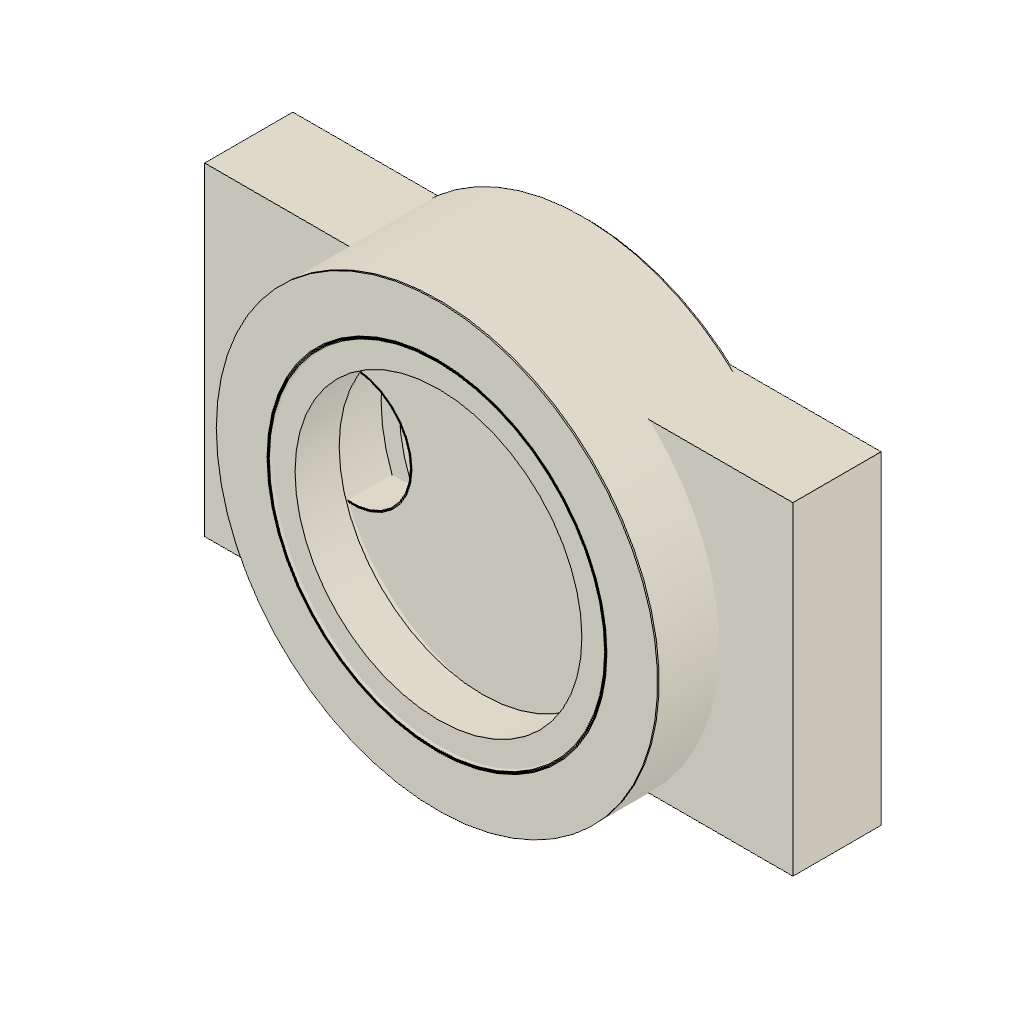
14-bearing-and-fastener-fit-trials (Autodesk Fusion 360 design; units mm, degrees)
part number: 2026-11-02-20-20-23-688
part number: 2026-11-02-20-20-23-889
part number: 2026-11-02-20-20-23-959
part number: 2026-11-02-20-20-24-041
part number: 2026-11-02-20-20-24-142
part number: 2026-11-02-20-20-24-261
part number: 2026-11-02-20-20-24-400
part number: 2026-11-02-20-20-24-565
part number: 2026-11-02-20-20-24-753
part number: 2026-11-02-20-20-24-962
part number: 2026-11-02-20-20-25-426
part number: 2026-11-02-20-20-25-979
Autodesk Fusion 360 part; units mm, degrees
ref_plane "WorkPlane1" through (0, 0, 0) normal (0, 0, 1) x (1, 0, 0)
ref_plane "WorkPlane1" through (0, 0, 0) normal (0, 0, 1) x (1, 0, 0) in component "Seat 22.0 mouth down"
sketch "Coupon Blank sketch" plane through (0, 0, 0) normal (0, 0, 1) x (1, 0, 0) in component "Seat 22.0 mouth down"
  circle A0 centre (0, 0) radius 15
  dimension "d10" = 30
  measures "d10" diameter of A0
extrude "Coupon Blank" add sketch "Coupon Blank sketch" along normal blind 10.1 makes body 1 in component "Seat 22.0 mouth down"
ref_plane "WorkPlane2" through (0, 0, 0) normal (0, 0, 1) x (1, 0, 0) in component "Seat 22.0 mouth down"
sketch "Seal Relief sketch" plane through (0, 0, 0) normal (0, 0, 1) x (1, 0, 0) in component "Seat 22.0 mouth down"
  circle A0 centre (0, 0) radius 9.75
  dimension "d15" = 19.5
  measures "d15" diameter of A0
extrude "Seal Relief" cut sketch "Seal Relief sketch" along normal blind 10.1 bodies 1 in component "Seat 22.0 mouth down"
ref_plane "WorkPlane3" through (0, 0, 0) normal (0, 0, 1) x (1, 0, 0) in component "Seat 22.0 mouth down"
sketch "Seat 22.0 sketch" plane through (0, 0, 0) normal (0, 0, 1) x (1, 0, 0) in component "Seat 22.0 mouth down"
  circle A0 centre (0, 0) radius 11
  dimension "d20" = 22
  measures "d20" diameter of A0
extrude "Seat 22.0" cut sketch "Seat 22.0 sketch" along normal blind 7.1 bodies 1 in component "Seat 22.0 mouth down"
chamfer "Pocket Entry" distance 0.4 angle 45 1 edges at (-10.2556, -3.9778, 0) tangent chain off on bodies 1 in component "Seat 22.0 mouth down"
chamfer "Outer Bed Relief" distance 0.3 angle 45 1 edges at (-13.9849, -5.4242, 0) tangent chain off on bodies 1 in component "Seat 22.0 mouth down"
ref_plane "WorkPlane1" through (0, 0, 0) normal (0, 0, 1) x (1, 0, 0) in component "Seat 22.1 mouth down"
sketch "Coupon Blank sketch (2)" plane through (0, 0, 0) normal (0, 0, 1) x (1, 0, 0) in component "Seat 22.1 mouth down"
  circle A0 centre (0, 0) radius 15
  dimension "d27" = 30
  measures "d27" diameter of A0
extrude "Coupon Blank'" add sketch "Coupon Blank sketch (2)" along normal blind 10.1 separate body makes body 2 in component "Seat 22.1 mouth down"
ref_plane "WorkPlane2" through (0, 0, 0) normal (0, 0, 1) x (1, 0, 0) in component "Seat 22.1 mouth down"
sketch "Seal Relief sketch (2)" plane through (0, 0, 0) normal (0, 0, 1) x (1, 0, 0) in component "Seat 22.1 mouth down"
  circle A0 centre (0, 0) radius 9.75
  dimension "d32" = 19.5
  measures "d32" diameter of A0
extrude "Seal Relief'" cut sketch "Seal Relief sketch (2)" along normal blind 10.1 bodies 2 in component "Seat 22.1 mouth down"
ref_plane "WorkPlane3" through (0, 0, 0) normal (0, 0, 1) x (1, 0, 0) in component "Seat 22.1 mouth down"
sketch "Seat 22.1 sketch" plane through (0, 0, 0) normal (0, 0, 1) x (1, 0, 0) in component "Seat 22.1 mouth down"
  circle A0 centre (0, 0) radius 11.05
  dimension "d37" = 22.1
  measures "d37" diameter of A0
extrude "Seat 22.1" cut sketch "Seat 22.1 sketch" along normal blind 7.1 bodies 2 in component "Seat 22.1 mouth down"
chamfer "Pocket Entry'" distance 0.4 angle 45 1 edges at (-10.3022, -3.9959, 0) tangent chain off on bodies 2 in component "Seat 22.1 mouth down"
chamfer "Outer Bed Relief'" distance 0.3 angle 45 1 edges at (-13.9849, -5.4242, 0) tangent chain off on bodies 2 in component "Seat 22.1 mouth down"
ref_plane "WorkPlane1" through (0, 0, 0) normal (0, 0, 1) x (1, 0, 0) in component "Seat 22.2 mouth down"
sketch "Coupon Blank sketch (3)" plane through (0, 0, 0) normal (0, 0, 1) x (1, 0, 0) in component "Seat 22.2 mouth down"
  circle A0 centre (0, 0) radius 15
  dimension "d44" = 30
  measures "d44" diameter of A0
extrude "Coupon Blank''" add sketch "Coupon Blank sketch (3)" along normal blind 10.1 separate body makes body 3 in component "Seat 22.2 mouth down"
ref_plane "WorkPlane2" through (0, 0, 0) normal (0, 0, 1) x (1, 0, 0) in component "Seat 22.2 mouth down"
sketch "Seal Relief sketch (3)" plane through (0, 0, 0) normal (0, 0, 1) x (1, 0, 0) in component "Seat 22.2 mouth down"
  circle A0 centre (0, 0) radius 9.75
  dimension "d49" = 19.5
  measures "d49" diameter of A0
extrude "Seal Relief''" cut sketch "Seal Relief sketch (3)" along normal blind 10.1 bodies 3 in component "Seat 22.2 mouth down"
ref_plane "WorkPlane3" through (0, 0, 0) normal (0, 0, 1) x (1, 0, 0) in component "Seat 22.2 mouth down"
sketch "Seat 22.2 sketch" plane through (0, 0, 0) normal (0, 0, 1) x (1, 0, 0) in component "Seat 22.2 mouth down"
  circle A0 centre (0, 0) radius 11.1
  dimension "d54" = 22.2
  measures "d54" diameter of A0
extrude "Seat 22.2" cut sketch "Seat 22.2 sketch" along normal blind 7.1 bodies 3 in component "Seat 22.2 mouth down"
chamfer "Pocket Entry''" distance 0.4 angle 45 1 edges at (-10.3488, -4.0139, 0) tangent chain off on bodies 3 in component "Seat 22.2 mouth down"
chamfer "Outer Bed Relief''" distance 0.3 angle 45 1 edges at (-13.9849, -5.4242, 0) tangent chain off on bodies 3 in component "Seat 22.2 mouth down"
ref_plane "WorkPlane1" through (0, 0, 0) normal (0, 0, 1) x (1, 0, 0) in component "Seat 22.3 mouth down"
sketch "Coupon Blank sketch (4)" plane through (0, 0, 0) normal (0, 0, 1) x (1, 0, 0) in component "Seat 22.3 mouth down"
  circle A0 centre (0, 0) radius 15
  dimension "d61" = 30
  measures "d61" diameter of A0
extrude "Coupon Blank'''" add sketch "Coupon Blank sketch (4)" along normal blind 10.1 separate body makes body 4 in component "Seat 22.3 mouth down"
ref_plane "WorkPlane2" through (0, 0, 0) normal (0, 0, 1) x (1, 0, 0) in component "Seat 22.3 mouth down"
sketch "Seal Relief sketch (4)" plane through (0, 0, 0) normal (0, 0, 1) x (1, 0, 0) in component "Seat 22.3 mouth down"
  circle A0 centre (0, 0) radius 9.75
  dimension "d66" = 19.5
  measures "d66" diameter of A0
extrude "Seal Relief'''" cut sketch "Seal Relief sketch (4)" along normal blind 10.1 bodies 4 in component "Seat 22.3 mouth down"
ref_plane "WorkPlane3" through (0, 0, 0) normal (0, 0, 1) x (1, 0, 0) in component "Seat 22.3 mouth down"
sketch "Seat 22.3 sketch" plane through (0, 0, 0) normal (0, 0, 1) x (1, 0, 0) in component "Seat 22.3 mouth down"
  circle A0 centre (0, 0) radius 11.15
  dimension "d71" = 22.3
  measures "d71" diameter of A0
extrude "Seat 22.3" cut sketch "Seat 22.3 sketch" along normal blind 7.1 bodies 4 in component "Seat 22.3 mouth down"
chamfer "Pocket Entry'''" distance 0.4 angle 45 1 edges at (-10.3954, -4.032, 0) tangent chain off on bodies 4 in component "Seat 22.3 mouth down"
chamfer "Outer Bed Relief'''" distance 0.3 angle 45 1 edges at (-13.9849, -5.4242, 0) tangent chain off on bodies 4 in component "Seat 22.3 mouth down"
ref_plane "WorkPlane1" through (0, 0, 0) normal (0, 0, 1) x (1, 0, 0) in component "Seat 22.0 mouth up"
sketch "Coupon Blank sketch (5)" plane through (0, 0, 0) normal (0, 0, 1) x (1, 0, 0) in component "Seat 22.0 mouth up"
  circle A0 centre (0, 0) radius 15
  dimension "d78" = 30
  measures "d78" diameter of A0
extrude "Coupon Blank''''" add sketch "Coupon Blank sketch (5)" along normal blind 10.2 separate body makes body 5 in component "Seat 22.0 mouth up"
ref_plane "WorkPlane2" through (0, 0, 0) normal (0, 0, 1) x (1, 0, 0) in component "Seat 22.0 mouth up"
sketch "Seal Relief sketch (5)" plane through (0, 0, 0) normal (0, 0, 1) x (1, 0, 0) in component "Seat 22.0 mouth up"
  circle A0 centre (0, 0) radius 9.75
  dimension "d83" = 19.5
  measures "d83" diameter of A0
extrude "Seal Relief''''" cut sketch "Seal Relief sketch (5)" along normal blind 10.2 bodies 5 in component "Seat 22.0 mouth up"
ref_plane "WorkPlane3" through (0, 0, 3) normal (0, 0, 1) x (1, 0, 0) in component "Seat 22.0 mouth up"
sketch "Seat 22.0 sketch (2)" plane through (0, 0, 3) normal (0, 0, 1) x (1, 0, 0) in component "Seat 22.0 mouth up"
  circle A0 centre (0, 0) radius 11
  dimension "d88" = 22
  measures "d88" diameter of A0
extrude "Seat 22.0'" cut sketch "Seat 22.0 sketch (2)" along normal blind 7.2 bodies 5 in component "Seat 22.0 mouth up"
chamfer "Pocket Entry''''" distance 0.4 angle 45 1 edges at (-10.2556, 3.9778, 10.2) tangent chain off on bodies 5 in component "Seat 22.0 mouth up"
chamfer "Outer Bed Relief''''" distance 0.3 angle 45 1 edges at (-13.9849, -5.4242, 0) tangent chain off on bodies 5 in component "Seat 22.0 mouth up"
ref_plane "WorkPlane1" through (0, 0, 0) normal (0, 0, 1) x (1, 0, 0) in component "Seat 22.1 mouth up"
sketch "Coupon Blank sketch (6)" plane through (0, 0, 0) normal (0, 0, 1) x (1, 0, 0) in component "Seat 22.1 mouth up"
  circle A0 centre (0, 0) radius 15
  dimension "d95" = 30
  measures "d95" diameter of A0
extrude "Coupon Blank'''''" add sketch "Coupon Blank sketch (6)" along normal blind 10.2 separate body makes body 6 in component "Seat 22.1 mouth up"
ref_plane "WorkPlane2" through (0, 0, 0) normal (0, 0, 1) x (1, 0, 0) in component "Seat 22.1 mouth up"
sketch "Seal Relief sketch (6)" plane through (0, 0, 0) normal (0, 0, 1) x (1, 0, 0) in component "Seat 22.1 mouth up"
  circle A0 centre (0, 0) radius 9.75
  dimension "d100" = 19.5
  measures "d100" diameter of A0
extrude "Seal Relief'''''" cut sketch "Seal Relief sketch (6)" along normal blind 10.2 bodies 6 in component "Seat 22.1 mouth up"
ref_plane "WorkPlane3" through (0, 0, 3) normal (0, 0, 1) x (1, 0, 0) in component "Seat 22.1 mouth up"
sketch "Seat 22.1 sketch (2)" plane through (0, 0, 3) normal (0, 0, 1) x (1, 0, 0) in component "Seat 22.1 mouth up"
  circle A0 centre (0, 0) radius 11.05
  dimension "d105" = 22.1
  measures "d105" diameter of A0
extrude "Seat 22.1'" cut sketch "Seat 22.1 sketch (2)" along normal blind 7.2 bodies 6 in component "Seat 22.1 mouth up"
chamfer "Pocket Entry'''''" distance 0.4 angle 45 1 edges at (-10.3022, 3.9959, 10.2) tangent chain off on bodies 6 in component "Seat 22.1 mouth up"
chamfer "Outer Bed Relief'''''" distance 0.3 angle 45 1 edges at (-13.9849, -5.4242, 0) tangent chain off on bodies 6 in component "Seat 22.1 mouth up"
ref_plane "WorkPlane1" through (0, 0, 0) normal (0, 0, 1) x (1, 0, 0) in component "Seat 22.2 mouth up"
sketch "Coupon Blank sketch (7)" plane through (0, 0, 0) normal (0, 0, 1) x (1, 0, 0) in component "Seat 22.2 mouth up"
  circle A0 centre (0, 0) radius 15
  dimension "d112" = 30
  measures "d112" diameter of A0
extrude "Coupon Blank''''''" add sketch "Coupon Blank sketch (7)" along normal blind 10.2 separate body makes body 7 in component "Seat 22.2 mouth up"
ref_plane "WorkPlane2" through (0, 0, 0) normal (0, 0, 1) x (1, 0, 0) in component "Seat 22.2 mouth up"
sketch "Seal Relief sketch (7)" plane through (0, 0, 0) normal (0, 0, 1) x (1, 0, 0) in component "Seat 22.2 mouth up"
  circle A0 centre (0, 0) radius 9.75
  dimension "d117" = 19.5
  measures "d117" diameter of A0
extrude "Seal Relief''''''" cut sketch "Seal Relief sketch (7)" along normal blind 10.2 bodies 7 in component "Seat 22.2 mouth up"
ref_plane "WorkPlane3" through (0, 0, 3) normal (0, 0, 1) x (1, 0, 0) in component "Seat 22.2 mouth up"
sketch "Seat 22.2 sketch (2)" plane through (0, 0, 3) normal (0, 0, 1) x (1, 0, 0) in component "Seat 22.2 mouth up"
  circle A0 centre (0, 0) radius 11.1
  dimension "d122" = 22.2
  measures "d122" diameter of A0
extrude "Seat 22.2'" cut sketch "Seat 22.2 sketch (2)" along normal blind 7.2 bodies 7 in component "Seat 22.2 mouth up"
chamfer "Pocket Entry''''''" distance 0.4 angle 45 1 edges at (-10.3488, 4.0139, 10.2) tangent chain off on bodies 7 in component "Seat 22.2 mouth up"
chamfer "Outer Bed Relief''''''" distance 0.3 angle 45 1 edges at (-13.9849, -5.4242, 0) tangent chain off on bodies 7 in component "Seat 22.2 mouth up"
ref_plane "WorkPlane1" through (0, 0, 0) normal (0, 0, 1) x (1, 0, 0) in component "Seat 22.3 mouth up"
sketch "Coupon Blank sketch (8)" plane through (0, 0, 0) normal (0, 0, 1) x (1, 0, 0) in component "Seat 22.3 mouth up"
  circle A0 centre (0, 0) radius 15
  dimension "d129" = 30
  measures "d129" diameter of A0
extrude "Coupon Blank'''''''" add sketch "Coupon Blank sketch (8)" along normal blind 10.2 separate body makes body 8 in component "Seat 22.3 mouth up"
ref_plane "WorkPlane2" through (0, 0, 0) normal (0, 0, 1) x (1, 0, 0) in component "Seat 22.3 mouth up"
sketch "Seal Relief sketch (8)" plane through (0, 0, 0) normal (0, 0, 1) x (1, 0, 0) in component "Seat 22.3 mouth up"
  circle A0 centre (0, 0) radius 9.75
  dimension "d134" = 19.5
  measures "d134" diameter of A0
extrude "Seal Relief'''''''" cut sketch "Seal Relief sketch (8)" along normal blind 10.2 bodies 8 in component "Seat 22.3 mouth up"
ref_plane "WorkPlane3" through (0, 0, 3) normal (0, 0, 1) x (1, 0, 0) in component "Seat 22.3 mouth up"
sketch "Seat 22.3 sketch (2)" plane through (0, 0, 3) normal (0, 0, 1) x (1, 0, 0) in component "Seat 22.3 mouth up"
  circle A0 centre (0, 0) radius 11.15
  dimension "d139" = 22.3
  measures "d139" diameter of A0
extrude "Seat 22.3'" cut sketch "Seat 22.3 sketch (2)" along normal blind 7.2 bodies 8 in component "Seat 22.3 mouth up"
chamfer "Pocket Entry'''''''" distance 0.4 angle 45 1 edges at (-10.3954, 4.032, 10.2) tangent chain off on bodies 8 in component "Seat 22.3 mouth up"
chamfer "Outer Bed Relief'''''''" distance 0.3 angle 45 1 edges at (-13.9849, -5.4242, 0) tangent chain off on bodies 8 in component "Seat 22.3 mouth up"
sketch "Trial Block" plane through (0, 0, 0) normal (0, 0, 1) x (1, 0, 0) in component "Sleeve 8.0 and Nut 7.0 Trial"
  line L0 (-20, -11) -> (20, -11)
  line L1 (20, -11) -> (20, 11)
  line L2 (20, 11) -> (-20, 11)
  line L3 (-20, 11) -> (-20, -11)
  line L4 (-20, -11) -> (20, 11) construction
  dimension "d144" = 40
  dimension "d145" = 22
  constraint horizontal L0
  constraint vertical L1
  constraint horizontal L2
  constraint vertical L3
  constraint midpoint origin L4
  measures "d144" distance of L0.start L0.end
  measures "d145" distance of L0.end L1.end
extrude "Six mm Trial Block" add sketch "Trial Block" along normal blind 6 separate body makes body 9 in component "Sleeve 8.0 and Nut 7.0 Trial"
sketch "Sleeve Trial" plane through (0, 0, 0) normal (0, 0, 1) x (1, 0, 0) in component "Sleeve 8.0 and Nut 7.0 Trial"
  circle A0 centre (-10, 0) radius 4
  line L0 (0, 0) -> (-10, 0) construction
  dimension "d148" = 10
  dimension "d149" = 8
  constraint horizontal L0
  measures "d148" distance of L0.start A0.centre
  measures "d149" diameter of A0
extrude "Sleeve Through Hole" cut sketch "Sleeve Trial" along normal blind 6 bodies 9 in component "Sleeve 8.0 and Nut 7.0 Trial"
sketch "Bolt Clearance" plane through (0, 0, 0) normal (0, 0, 1) x (1, 0, 0) in component "Sleeve 8.0 and Nut 7.0 Trial"
  circle A0 centre (10, 0) radius 2.15
  line L0 (0, 0) -> (10, 0) construction
  dimension "d152" = 10
  dimension "d153" = 4.3
  constraint horizontal L0
  measures "d152" distance of L0.start A0.centre
  measures "d153" diameter of A0
extrude "M4 Through Hole" cut sketch "Bolt Clearance" along normal blind 6 bodies 9 in component "Sleeve 8.0 and Nut 7.0 Trial"
sketch "Nut Trial" plane through (0, 0, 0) normal (0, 0, 1) x (1, 0, 0) in component "Sleeve 8.0 and Nut 7.0 Trial"
  line L0 (0, 0) -> (10, 0) construction
  circle A0 centre (10, 0) radius 4.0415 construction
  line L1 (14.0415, 0) -> (12.0207, 3.5)
  line L2 (12.0207, 3.5) -> (7.9793, 3.5)
  line L3 (7.9793, 3.5) -> (5.9585, 0)
  line L4 (5.9585, 0) -> (7.9793, -3.5)
  line L5 (7.9793, -3.5) -> (12.0207, -3.5)
  line L6 (12.0207, -3.5) -> (14.0415, 0)
  dimension "d156" = 10
  dimension "d157" = 8.0829
  constraint horizontal L0
  constraint coincident A0 L1.start
  constraint coincident A0 L1.end
  constraint coincident A0 L2.end
  constraint coincident A0 L3.end
  constraint coincident A0 L4.end
  constraint coincident A0 L5.end
  constraint equal L1 L2
  constraint equal L1 L3
  constraint equal L1 L4
  constraint equal L1 L5
  constraint equal L1 L6
  constraint horizontal L2
  measures "d156" distance of L0.start L0.end
  measures "d157" diameter of A0
extrude "Nut Pocket Opening Down" cut sketch "Nut Trial" along normal blind 4 bodies 9 in component "Sleeve 8.0 and Nut 7.0 Trial"
sketch "Trial Block (2)" plane through (0, 0, 0) normal (0, 0, 1) x (1, 0, 0) in component "Sleeve 8.1 and Nut 7.1 Trial"
  line L0 (-20, -11) -> (20, -11)
  line L1 (20, -11) -> (20, 11)
  line L2 (20, 11) -> (-20, 11)
  line L3 (-20, 11) -> (-20, -11)
  line L4 (-20, -11) -> (20, 11) construction
  dimension "d160" = 40
  dimension "d161" = 22
  constraint horizontal L0
  constraint vertical L1
  constraint horizontal L2
  constraint vertical L3
  constraint midpoint origin L4
  measures "d160" distance of L0.start L0.end
  measures "d161" distance of L0.end L1.end
extrude "Six mm Trial Block'" add sketch "Trial Block (2)" along normal blind 6 separate body makes body 10 in component "Sleeve 8.1 and Nut 7.1 Trial"
sketch "Sleeve Trial (2)" plane through (0, 0, 0) normal (0, 0, 1) x (1, 0, 0) in component "Sleeve 8.1 and Nut 7.1 Trial"
  circle A0 centre (-10, 0) radius 4.05
  line L0 (0, 0) -> (-10, 0) construction
  dimension "d164" = 10
  dimension "d165" = 8.1
  constraint horizontal L0
  measures "d164" distance of L0.start A0.centre
  measures "d165" diameter of A0
extrude "Sleeve Through Hole'" cut sketch "Sleeve Trial (2)" along normal blind 6 bodies 10 in component "Sleeve 8.1 and Nut 7.1 Trial"
sketch "Bolt Clearance (2)" plane through (0, 0, 0) normal (0, 0, 1) x (1, 0, 0) in component "Sleeve 8.1 and Nut 7.1 Trial"
  circle A0 centre (10, 0) radius 2.15
  line L0 (0, 0) -> (10, 0) construction
  dimension "d168" = 10
  dimension "d169" = 4.3
  constraint horizontal L0
  measures "d168" distance of L0.start A0.centre
  measures "d169" diameter of A0
extrude "M4 Through Hole'" cut sketch "Bolt Clearance (2)" along normal blind 6 bodies 10 in component "Sleeve 8.1 and Nut 7.1 Trial"
sketch "Nut Trial (2)" plane through (0, 0, 0) normal (0, 0, 1) x (1, 0, 0) in component "Sleeve 8.1 and Nut 7.1 Trial"
  line L0 (0, 0) -> (10, 0) construction
  circle A0 centre (10, 0) radius 4.0992 construction
  line L1 (14.0992, 0) -> (12.0496, 3.55)
  line L2 (12.0496, 3.55) -> (7.9504, 3.55)
  line L3 (7.9504, 3.55) -> (5.9008, 0)
  line L4 (5.9008, 0) -> (7.9504, -3.55)
  line L5 (7.9504, -3.55) -> (12.0496, -3.55)
  line L6 (12.0496, -3.55) -> (14.0992, 0)
  dimension "d172" = 10
  dimension "d173" = 8.1984
  constraint horizontal L0
  constraint coincident A0 L1.start
  constraint coincident A0 L1.end
  constraint coincident A0 L2.end
  constraint coincident A0 L3.end
  constraint coincident A0 L4.end
  constraint coincident A0 L5.end
  constraint equal L1 L2
  constraint equal L1 L3
  constraint equal L1 L4
  constraint equal L1 L5
  constraint equal L1 L6
  constraint horizontal L2
  measures "d172" distance of L0.start L0.end
  measures "d173" diameter of A0
extrude "Nut Pocket Opening Down'" cut sketch "Nut Trial (2)" along normal blind 4 bodies 10 in component "Sleeve 8.1 and Nut 7.1 Trial"
sketch "Trial Block (3)" plane through (0, 0, 0) normal (0, 0, 1) x (1, 0, 0) in component "Sleeve 8.2 and Nut 7.2 Trial"
  line L0 (-20, -11) -> (20, -11)
  line L1 (20, -11) -> (20, 11)
  line L2 (20, 11) -> (-20, 11)
  line L3 (-20, 11) -> (-20, -11)
  line L4 (-20, -11) -> (20, 11) construction
  dimension "d176" = 40
  dimension "d177" = 22
  constraint horizontal L0
  constraint vertical L1
  constraint horizontal L2
  constraint vertical L3
  constraint midpoint origin L4
  measures "d176" distance of L0.start L0.end
  measures "d177" distance of L0.end L1.end
extrude "Six mm Trial Block''" add sketch "Trial Block (3)" along normal blind 6 separate body makes body 11 in component "Sleeve 8.2 and Nut 7.2 Trial"
sketch "Sleeve Trial (3)" plane through (0, 0, 0) normal (0, 0, 1) x (1, 0, 0) in component "Sleeve 8.2 and Nut 7.2 Trial"
  circle A0 centre (-10, 0) radius 4.1
  line L0 (0, 0) -> (-10, 0) construction
  dimension "d180" = 10
  dimension "d181" = 8.2
  constraint horizontal L0
  measures "d180" distance of L0.start A0.centre
  measures "d181" diameter of A0
extrude "Sleeve Through Hole''" cut sketch "Sleeve Trial (3)" along normal blind 6 bodies 11 in component "Sleeve 8.2 and Nut 7.2 Trial"
sketch "Bolt Clearance (3)" plane through (0, 0, 0) normal (0, 0, 1) x (1, 0, 0) in component "Sleeve 8.2 and Nut 7.2 Trial"
  circle A0 centre (10, 0) radius 2.15
  line L0 (0, 0) -> (10, 0) construction
  dimension "d184" = 10
  dimension "d185" = 4.3
  constraint horizontal L0
  measures "d184" distance of L0.start A0.centre
  measures "d185" diameter of A0
extrude "M4 Through Hole''" cut sketch "Bolt Clearance (3)" along normal blind 6 bodies 11 in component "Sleeve 8.2 and Nut 7.2 Trial"
sketch "Nut Trial (3)" plane through (0, 0, 0) normal (0, 0, 1) x (1, 0, 0) in component "Sleeve 8.2 and Nut 7.2 Trial"
  line L0 (0, 0) -> (10, 0) construction
  circle A0 centre (10, 0) radius 4.1569 construction
  line L1 (14.1569, 0) -> (12.0785, 3.6)
  line L2 (12.0785, 3.6) -> (7.9215, 3.6)
  line L3 (7.9215, 3.6) -> (5.8431, 0)
  line L4 (5.8431, 0) -> (7.9215, -3.6)
  line L5 (7.9215, -3.6) -> (12.0785, -3.6)
  line L6 (12.0785, -3.6) -> (14.1569, 0)
  dimension "d188" = 10
  dimension "d189" = 8.3138
  constraint horizontal L0
  constraint coincident A0 L1.start
  constraint coincident A0 L1.end
  constraint coincident A0 L2.end
  constraint coincident A0 L3.end
  constraint coincident A0 L4.end
  constraint coincident A0 L5.end
  constraint equal L1 L2
  constraint equal L1 L3
  constraint equal L1 L4
  constraint equal L1 L5
  constraint equal L1 L6
  constraint horizontal L2
  measures "d188" distance of L0.start L0.end
  measures "d189" diameter of A0
extrude "Nut Pocket Opening Down''" cut sketch "Nut Trial (3)" along normal blind 4 bodies 11 in component "Sleeve 8.2 and Nut 7.2 Trial"
chamfer "Sleeve Bed Entry Lead In" distance 0.3 angle 45 1 edges at (-13.7293, -1.4465, 0) tangent chain off on bodies 9 in component "Sleeve 8.0 and Nut 7.0 Trial"
chamfer "Nut Pocket Bed Entry Lead In" distance 0.3 angle 45 6 edges at (10, -3.5, 0) (13.0311, -1.75, 0) (13.0311, 1.75, 0) (10, 3.5, 0) (6.9689, 1.75, 0) (6.9689, -1.75, 0) tangent chain off on bodies 9 in component "Sleeve 8.0 and Nut 7.0 Trial"
chamfer "Sleeve Bed Entry Lead In'" distance 0.3 angle 45 1 edges at (-13.7759, -1.4645, 0) tangent chain off on bodies 10 in component "Sleeve 8.1 and Nut 7.1 Trial"
chamfer "Nut Pocket Bed Entry Lead In'" distance 0.3 angle 45 6 edges at (10, -3.55, 0) (13.0744, -1.775, 0) (13.0744, 1.775, 0) (10, 3.55, 0) (6.9256, 1.775, 0) (6.9256, -1.775, 0) tangent chain off on bodies 10 in component "Sleeve 8.1 and Nut 7.1 Trial"
chamfer "Sleeve Bed Entry Lead In''" distance 0.3 angle 45 1 edges at (-13.8225, -1.4826, 0) tangent chain off on bodies 11 in component "Sleeve 8.2 and Nut 7.2 Trial"
chamfer "Nut Pocket Bed Entry Lead In''" distance 0.3 angle 45 6 edges at (10, -3.6, 0) (13.1177, -1.8, 0) (13.1177, 1.8, 0) (10, 3.6, 0) (6.8823, 1.8, 0) (6.8823, -1.8, 0) tangent chain off on bodies 11 in component "Sleeve 8.2 and Nut 7.2 Trial"
component "Seat 22.0 mouth down" placed x (1, 0, 0) y (0, 1, 0) z (0, 0, 1) at (0, 0, 0)
component "Seat 22.1 mouth down" placed x (1, 0, 0) y (0, 1, 0) z (0, 0, 1) at (0, 0, 0)
component "Seat 22.2 mouth down" placed x (1, 0, 0) y (0, 1, 0) z (0, 0, 1) at (0, 0, 0)
component "Seat 22.3 mouth down" placed x (1, 0, 0) y (0, 1, 0) z (0, 0, 1) at (0, 0, 0)
component "Seat 22.0 mouth up" placed x (1, 0, 0) y (0, 1, 0) z (0, 0, 1) at (0, 0, 0)
component "Seat 22.1 mouth up" placed x (1, 0, 0) y (0, 1, 0) z (0, 0, 1) at (0, 0, 0)
component "Seat 22.2 mouth up" placed x (1, 0, 0) y (0, 1, 0) z (0, 0, 1) at (0, 0, 0)
component "Seat 22.3 mouth up" placed x (1, 0, 0) y (0, 1, 0) z (0, 0, 1) at (0, 0, 0)
component "Sleeve 8.0 and Nut 7.0 Trial" placed x (1, 0, 0) y (0, 1, 0) z (0, 0, 1) at (0, 0, 0)
component "Sleeve 8.1 and Nut 7.1 Trial" placed x (1, 0, 0) y (0, 1, 0) z (0, 0, 1) at (0, 0, 0)
component "Sleeve 8.2 and Nut 7.2 Trial" placed x (1, 0, 0) y (0, 1, 0) z (0, 0, 1) at (0, 0, 0)
equation "bearingDiameter = 22 mm" comment "Nominal 608 outside diameter."
equation "entry = 0.4 mm" comment "Bearing mouth chamfer."
equation "bed = 0.3 mm" comment "Bed edge relief."
equation "nutAF = 7.2 mm" comment "Trial nut AF."
equation "nutDepth = 4 mm" comment "Nut pocket depth."
equation "d23 = entry"
equation "d24 = bed"
equation "d40 = entry"
equation "d41 = bed"
equation "d57 = entry"
equation "d58 = bed"
equation "d74 = entry"
equation "d75 = bed"
equation "d91 = entry"
equation "d92 = bed"
equation "d108 = entry"
equation "d109 = bed"
equation "d125 = entry"
equation "d126 = bed"
equation "d142 = entry"
equation "d143 = bed"
equation "d148 = abs(-10 mm)"
equation "d152 = abs(10 mm)"
equation "d156 = abs(10 mm)"
equation "d157 = 2 * ( 7.0 mm ) / sqrt(3)"
equation "d158 = nutDepth"
equation "d164 = abs(-10 mm)"
equation "d168 = abs(10 mm)"
equation "d172 = abs(10 mm)"
equation "d173 = 2 * ( 7.1 mm ) / sqrt(3)"
equation "d174 = nutDepth"
equation "d180 = abs(-10 mm)"
equation "d184 = abs(10 mm)"
equation "d188 = abs(10 mm)"
equation "d189 = 2 * ( 7.2 mm ) / sqrt(3)"
equation "d190 = nutDepth"
equation "d192 = bed"
equation "d193 = bed"
equation "d194 = bed"
equation "d195 = bed"
equation "d196 = bed"
equation "d197 = bed"
